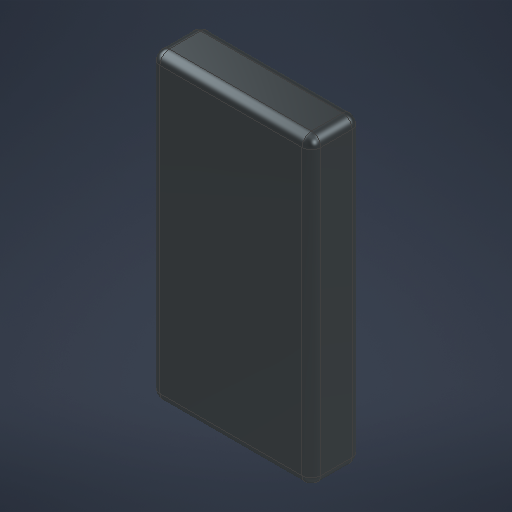
# Autodesk Inventor part: powerbank_537
Saved by Autodesk Inventor 2026.3 (Build 303398000, 398)
## iProperties
Created: 2026-07-18
Part Number: powerbank_537
Material: Generic
Document SubType Name: Modeling
Designer: nose
Density: 1 g/cm^3
Appearance: Default
Author: nose
Autodesk Inventor part; units mm, degrees
ref_plane "YZ Plane" through (0, 0, 0) normal (1, 0, 0) x (0, 1, 0)
ref_plane "XZ Plane" through (0, 0, 0) normal (0, 1, 0) x (-1, 0, 0)
ref_plane "XY Plane" through (0, 0, 0) normal (0, 0, 1) x (1, 0, 0)
sketch "Sketch1" plane through (0, 0, 0) normal (0, 0, 1) x (1, 0, 0)
  line L0 (42.5, -80) -> (-42.5, -80)
  line L1 (-42.5, -80) -> (-42.5, 80)
  line L2 (-42.5, 80) -> (42.5, 80)
  line L3 (42.5, 80) -> (42.5, -80)
  line L4 (42.5, -80) -> (-42.5, 80) construction
  line L5 (-42.5, -80) -> (42.5, 80) construction
  point P0 (0, 0)
  dimension "d0" = 85
  dimension "d1" = 160
  constraints: 12 end point, 2 midpoint, 2 parallel, 1 horizontal, 1 perpendicular
  measures "d0" distance of L1.end L2.end
  measures "d1" distance of L0.end L1.end
extrude "Extrusion1" add sketch "Sketch1" along normal blind 26.5
fillet "Fillet1" radius 5 12 edges at (42.5, 0, 26.5) (42.5, 0, 0) (0, 80, 26.5) (-42.5, 0, 26.5) (0, -80, 26.5) (0, -80, 0) (-42.5, 0, 0) (0, 80, 0) (-42.5, 80, 13.25) (42.5, 80, 13.25) (42.5, -80, 13.25) (-42.5, -80, 13.25)
equation "\"d0\" = powerbank_width"
equation "\"d1\" = powerbank_length"
equation "\"d2\" = powerbank_thick"
equation "\"powerbank_width\" = 85"
equation "\"powerbank_length\" = 160"
equation "\"powerbank_thick\" = 26.5"
body "Solid1"
